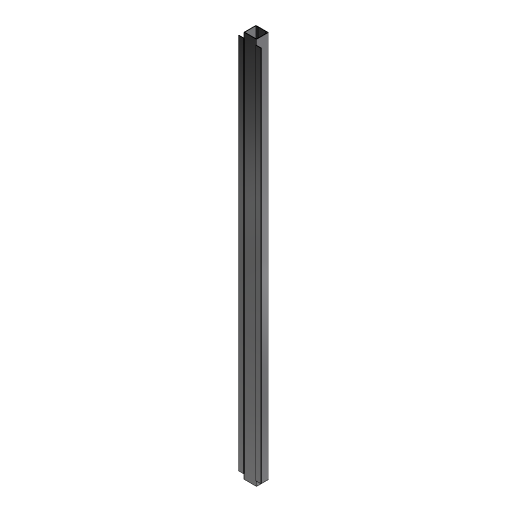
# Autodesk Inventor part: P350 1550mm gefräst
Saved by Autodesk Inventor 2024.3 (Build 283343000, 343)
## iProperties
Created: 2023-06-01
Part Number: P350 1550mm gefräst
Material: Aluminium 6061
Document SubType Name: Modeling
Designer: FarhadPabel
Density: 2.7 g/cm^3
Appearance: Aluminium - flach
Description: Omega-Profil
Mass: 1645.86 g
Surface Area: 7177.9 cm^2
Volume: 609.577 cm^3
Bemerkung: Sägen
Author: FarhadPabel
Autodesk Inventor part; units mm, degrees
ref_plane "YZ Plane" through (0, 0, 0) normal (1, 0, 0) x (0, 1, 0)
ref_plane "XZ Plane" through (0, 0, 0) normal (0, 1, 0) x (-1, 0, 0)
sketch "Skizze1" plane through (0, 0, 0) normal (0, 0, 1) x (1, 0, 0)
  arc A0 (24.4982, 21.3547) -> (23.4982, 22.3547) centre (23.4982, 21.3547) ccw
  line L0 (-24.5018, 22.3547) -> (23.4982, 22.3547)
  arc A1 (-24.5018, 22.3547) -> (-25.5018, 21.3547) centre (-24.5018, 21.3547) ccw
  line L1 (-25.5018, -25.6453) -> (-25.5018, 21.3547)
  line L2 (-45.5018, -25.6453) -> (-25.5018, -25.6453)
  line L3 (-45.5018, -27.3453) -> (-45.5018, -25.6453)
  line L4 (-24.8018, -27.3453) -> (-45.5018, -27.3453)
  arc A2 (-24.8018, -27.3453) -> (-23.8018, -26.3453) centre (-24.8018, -26.3453) ccw
  line L5 (-23.8018, -25.5448) -> (-23.8018, -26.3453)
  line L6 (22.7982, -25.5448) -> (-23.8018, -25.5448)
  line L7 (22.7982, -26.3453) -> (22.7982, -25.5448)
  arc A3 (22.7982, -26.3453) -> (23.7982, -27.3453) centre (23.7982, -26.3453) ccw
  line L8 (44.4982, -27.3453) -> (23.7982, -27.3453)
  line L9 (44.4982, -25.6453) -> (44.4982, -27.3453)
  line L10 (24.4982, -25.6453) -> (44.4982, -25.6453)
  line L11 (24.4982, 21.3547) -> (24.4982, -25.6453)
  line L12 (-15.8018, 20.2547) -> (-15.4018, 20.6547)
  line L13 (-15.4018, 20.6547) -> (14.3982, 20.6547)
  line L14 (14.3982, 20.6547) -> (14.7926, 20.2547)
  line L15 (14.7926, 20.2547) -> (15.1926, 20.6547)
  line L16 (15.1926, 20.6547) -> (22.7982, 20.6547)
  line L17 (22.7982, 20.6547) -> (22.7982, -23.8453)
  line L18 (22.7982, -23.8453) -> (15.1926, -23.8453)
  line L19 (15.1926, -23.8453) -> (14.7926, -23.4453)
  line L20 (14.7926, -23.4453) -> (14.3926, -23.8453)
  line L21 (14.3926, -23.8453) -> (-15.4074, -23.8453)
  line L22 (-15.4074, -23.8453) -> (-15.8046, -23.4481)
  line L23 (-15.8046, -23.4481) -> (-16.2018, -23.8453)
  line L24 (-16.2018, -23.8453) -> (-23.8018, -23.8453)
  line L25 (-23.8018, -23.8453) -> (-23.8018, 20.6547)
  line L26 (-23.8018, 20.6547) -> (-16.2018, 20.6547)
  line L27 (-16.2018, 20.6547) -> (-15.8018, 20.2547)
  point P0 (0, 0)
  point P1 (-70.6649, -189.4661)
  constraints: 56 end point, 12 horizontal, 8 point on circle, 8 vertical, 4 centre point, 50 other
extrude "Extrusion1" add sketch "Skizze1" along normal blind 1550
ref_plane "Arbeitsebene1" through (0, 0, 775) normal (0, 0, 1) x (1, 0, 0)
sketch "Skizze2" plane through (23.7982, -27.3453, 0) normal (0, -1, 0) x (1, 0, 0)
  line L0 (-69.3, 1550) -> (-48.6, 1550) projected
  line L1 (-47.6, 0) -> (-47.6, 1550) projected
  line L2 (-69.3, 1550) -> (-47.6, 1550)
  line L3 (-47.6, 1550) -> (-47.6, 1530)
  line L4 (-47.6, 1530) -> (-69.3, 1530)
  line L5 (-69.3, 1530) -> (-69.3, 1550)
  line L6 (20.7, 0) -> (20.7, 1550) projected
  line L7 (-1, 0) -> (-1, 1550) projected
  line L8 (20.7, 1550) -> (-1, 1550)
  line L9 (-1, 1550) -> (-1, 1530)
  line L10 (-1, 1530) -> (20.7, 1530)
  line L11 (20.7, 1530) -> (20.7, 1550)
  line L12 (-69.3, 0) -> (-69.3, 1550) projected
  line L13 (-69.3, 0) -> (-47.6, 0)
  line L14 (-47.6, 0) -> (-47.6, 20)
  line L15 (-47.6, 20) -> (-69.3, 20)
  line L16 (-69.3, 20) -> (-69.3, 0)
  line L17 (20.7, 0) -> (-1, 0)
  line L18 (-1, 0) -> (-1, 20)
  line L19 (-1, 20) -> (20.7, 20)
  line L20 (20.7, 20) -> (20.7, 0)
  point P0 (-23.7982, 0)
  point P1 (20.7, 1530)
  point P2 (-69.3, 20)
  dimension "d2" = 20
  dimension "d3" = 20
  dimension "d4" = 20
  dimension "d5" = 20
  constraints: 32 end point, 8 parallel, 4 horizontal, 4 perpendicular, 4 point on line
  measures "d2" distance between parallel lines of L4 L0
  measures "d3" distance between parallel lines of L10 L8
  measures "d4" distance between parallel lines of L13 L15
  measures "d5" distance between parallel lines of L17 L19
extrude "Extrusion2" cut sketch "Skizze2" against normal up to surface (1.8004 mm away) contours L0 L2 L1 L4 L5 | L15 L1 L13 L12 | L17 L7 L19 L6 | L10 L7 L8 L6
equation "\"d6\" = d5"
